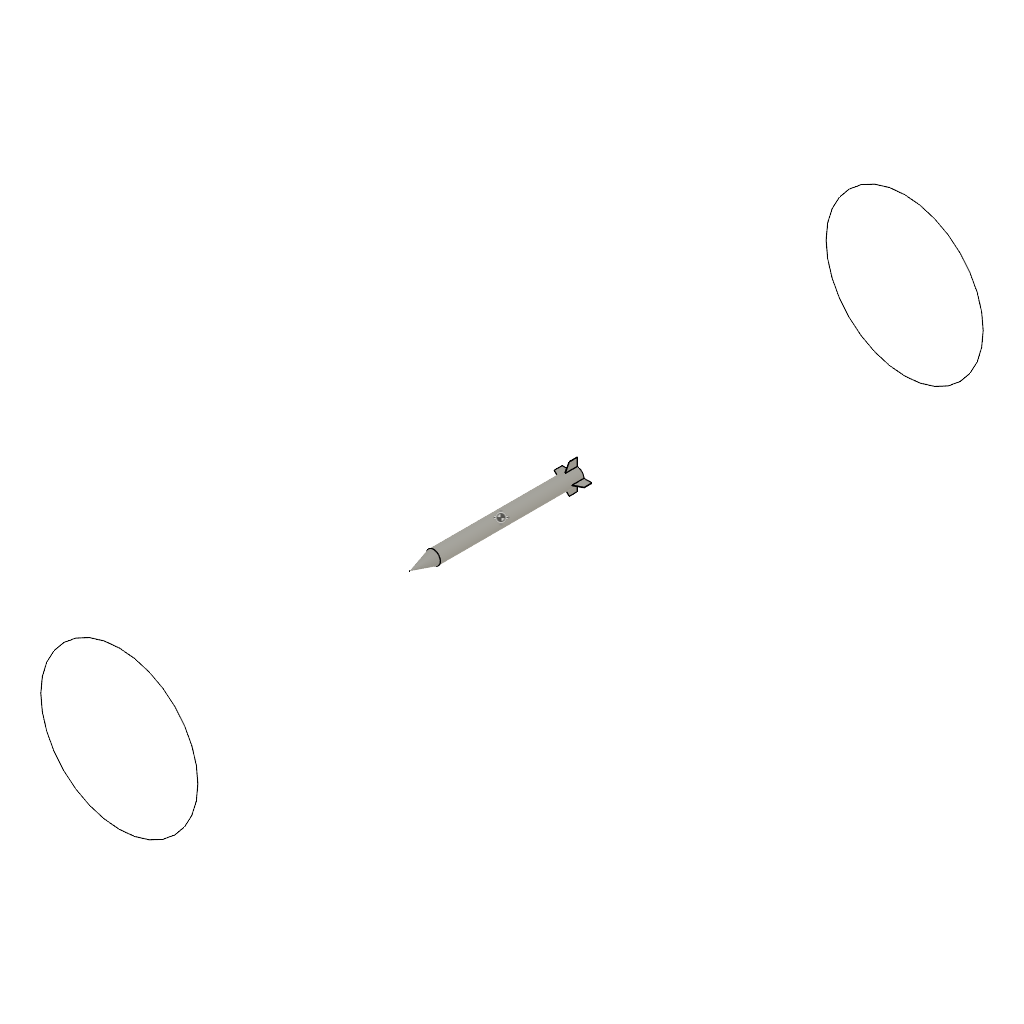
rocket test (Autodesk Fusion 360 design; units mm, degrees)
part number: 2026-10-11-15-20-58-729
Autodesk Fusion 360 part; units mm, degrees
sketch "Sketch1" plane through (0, 0, 0) normal (0, 1, 0) x (1, 0, 0)
  circle A0 centre (0, 0) radius 44.45
  circle A1 centre (0, 0) radius 500
  dimension "d1" = 88.9
  dimension "d27" = 1000
  constraint coincident A0.centre A1.centre
  constraint concentric A0 A1
  measures "d1" diameter of A0
  measures "d27" diameter of A1
extrude "Extrude5" add sketch "Sketch1" against normal blind 152.4 draft -16 contours A0 makes body 1
extrude "Extrude6" add sketch "Sketch1" along normal blind 914.4 separate body contours A0 makes body 2
sketch "Sketch3" plane through (0, 914.4, 0) normal (0, 1, 0) x (-1, 0, 0)
  circle A0 centre (0, 0) radius 44.45
  line L0 (-1.27, 95.2319) -> (1.27, 95.2319)
  line L1 (1.27, 95.2319) -> (1.27, 44.4319)
  line L2 (1.27, 44.4319) -> (-1.27, 44.4319)
  line L3 (-1.27, 44.4319) -> (-1.27, 95.2319)
  circle A1 centre (0, 0) radius 44.45
  dimension "d19" = 2.54
  dimension "d20" = 50.8
  constraint horizontal L0
  constraint vertical L1
  constraint horizontal L2
  constraint vertical L3
  constraint coincident L2.end A1
  constraint coincident L1.end A1
  measures "d19" distance of L1.end L2.end
  measures "d20" distance of L0.start L2.end
extrude "Extrude7" add sketch "Sketch3" against normal blind 76.2 separate body contours A0 L0 L1 L3 A1 makes body 3
chamfer "Chamfer2" distance 50.546 distance2 25.4 1 edges at (0, 838.2, 95.2319) measured on face at (0.1411, 838.2, 78.3039) tangent chain off on bodies 3
pattern_circular "C-Pattern2" count 4 over 360 about axis through (0, 0, 0) along (0, 1, 0) of bodies 3 makes body 4 at (61.4499, 872.0667, -1.27) makes body 5 at (-1.27, 872.0667, -61.4499) makes body 6 at (-61.4499, 872.0667, 1.27)
combine "Combine2" operation add target body 2 tool bodies 1 3 4 6 5
extrude "Extrude8" add sketch "Sketch1" along normal blind 3000 and the other way blind 2000 separate body contours A0 | A1 makes body 7
combine "Combine3" operation cut target body 7 tool bodies 2 keep tools
named bodies: "solid domain", "air domain"
